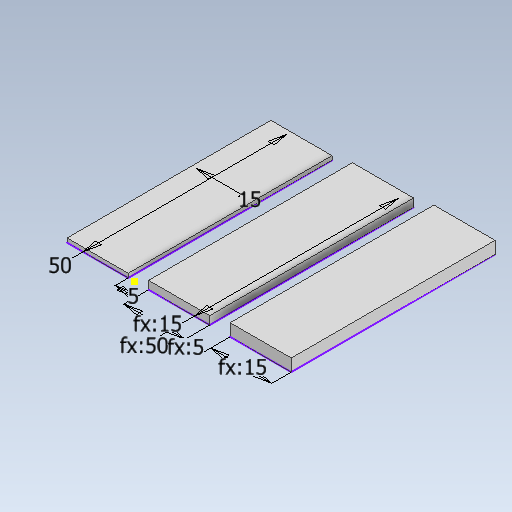
# Autodesk Inventor part: Test Strips
Saved by Autodesk Inventor 2026.4 (Build 304435000, 435)
## iProperties
Created: 2026-11-12
Part Number: Test Strips
Material: Generisch
Document SubType Name: Modeling
Designer: weira
Density: 1 g/cm^3
Appearance: Vorgabe
Author: weira
Autodesk Inventor part; units mm, degrees
ref_plane "YZ Plane" through (0, 0, 0) normal (1, 0, 0) x (0, 1, 0)
ref_plane "XZ Plane" through (0, 0, 0) normal (0, 1, 0) x (-1, 0, 0)
ref_plane "XY Plane" through (0, 0, 0) normal (0, 0, 1) x (1, 0, 0)
sketch "Skizze1" plane through (0, 0, 0) normal (0, 0, 1) x (1, 0, 0)
  line L0 (3.4449, 0) -> (18.4449, 0)
  line L1 (18.4449, 0) -> (18.4449, 50)
  line L2 (18.4449, 50) -> (3.4449, 50)
  line L3 (3.4449, 50) -> (3.4449, 0)
  line L4 (23.4449, 0) -> (38.4449, 0)
  line L5 (38.4449, 0) -> (38.4449, 50)
  line L6 (38.4449, 50) -> (23.4449, 50)
  line L7 (23.4449, 50) -> (23.4449, 0)
  line L8 (-16.5551, 0) -> (-1.5551, 0)
  line L9 (-1.5551, 0) -> (-1.5551, 50)
  line L10 (-1.5551, 50) -> (-16.5551, 50)
  line L11 (-16.5551, 50) -> (-16.5551, 0)
  point P0 (0, 0)
  dimension "d0" = 15
  dimension "d1" = 5
  dimension "d2" = 5
  dimension "d3" = 15
  dimension "d4" = 15
  dimension "d5" = 50
  dimension "d6" = 50
  constraints: 24 end point, 6 parallel, 3 horizontal, 3 perpendicular, 2 point on line
  measures "d0" distance between parallel lines of L9 L11
  measures "d1" distance between parallel lines of L3 L9
  measures "d2" distance between parallel lines of L7 L1
  measures "d3" distance between parallel lines of L1 L3
  measures "d4" distance between parallel lines of L5 L7
  measures "d5" distance between parallel lines of L0 L2
  measures "d6" distance between parallel lines of L8 L10
extrude "Extrusion1" add sketch "Skizze1" along normal blind 1 contours L11 L10 L9 L8
extrude "Extrusion2" add sketch "Skizze1" along normal blind 2 contours L3 L2 L1 L0
extrude "Extrusion3" add sketch "Skizze1" along normal blind 3 contours L7 L6 L5 L4
equation "\"d2\" = d1"
equation "\"d3\" = d0"
equation "\"d4\" = d3"
equation "\"d5\" = d6"
